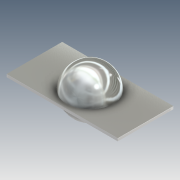
# Autodesk Inventor part: Materials Test Part
Saved by Autodesk Inventor 2020 (Build 240168000, 168)
## iProperties
Created: 2019-06-13
Part Number: Materials Test Part
Material: Generic
Document SubType Name: Modeling
Designer: PC
Mass: 3130.67 g
Surface Area: 2121.83 cm^2
Volume: 3130.67 cm^3
Density: 1 g/cm^3
Appearance: Default
Author: PC
Autodesk Inventor part; units mm, degrees
ref_plane "YZ Plane" through (0, 0, 0) normal (1, 0, 0) x (0, 1, 0)
ref_plane "XZ Plane" through (0, 0, 0) normal (0, 1, 0) x (-1, 0, 0)
ref_plane "XY Plane" through (0, 0, 0) normal (0, 0, 1) x (1, 0, 0)
sketch "Sketch4" plane through (0, 0, 0) normal (0, 0, 1) x (1, 0, 0)
  line L0 (-200, -100) -> (200, -100)
  line L1 (200, -100) -> (200, 100)
  line L2 (200, 100) -> (-200, 100)
  line L3 (-200, 100) -> (-200, -100)
  line L4 (-200, -100) -> (200, 100) construction
  line L5 (200, -100) -> (-200, 100) construction
  point P0 (0, 0)
  dimension "d7" = 200
  dimension "d8" = 400
  constraints: 12 end point, 2 midpoint, 2 parallel, 1 horizontal, 1 perpendicular
  measures "d7" distance of L2.end L0.start
  measures "d8" distance of L0.start L0.end
extrude "Extrusion1" add sketch "Sketch4" along normal blind 10
sketch "Sketch5" plane through (0, 0, 10) normal (0, 0, 1) x (1, 0, 0)
  point P0 (0, 0)
sketch "Sketch6" plane through (0, 0, 10) normal (0, 0, 1) x (1, 0, 0)
  circle A0 centre (0, 0) radius 84.8142
  line L0 (0, 84.8142) -> (0, -84.8142)
  constraints: 2 end point, 2 point on circle, 1 centre point, 1 coincident, 1 midpoint
revolve "Revolution3" add sketch "Sketch6" angle 360 about axis through (0, 84.8142, 10) along (0, -1, 0) picked at (-40.4588, 0.687) contours L0 A0
body "Solid3"
